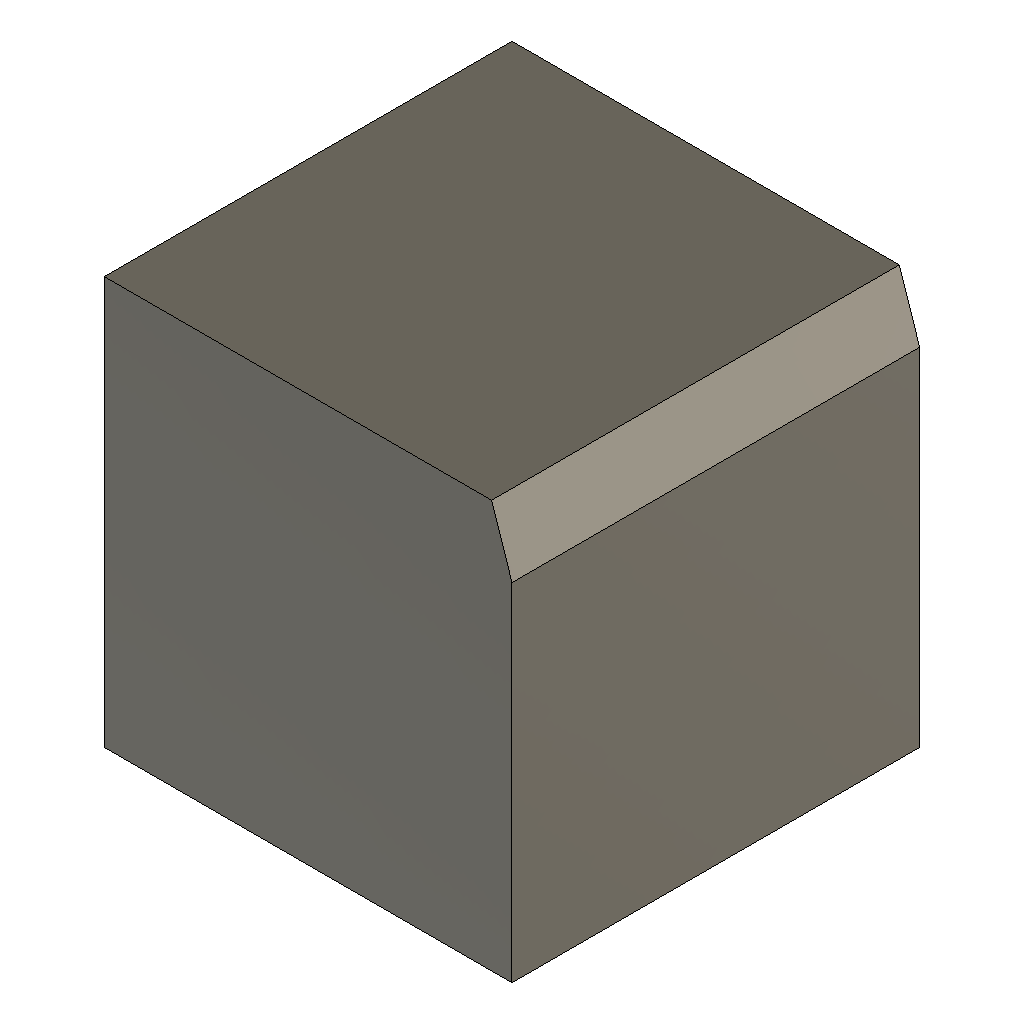
dr341-chamfer-box (Autodesk Fusion 360 design; units mm, degrees)
part number: 2026-11-15-17-11-38-125
Autodesk Fusion 360 part; units mm, degrees
box "BoxPrimitive1" add length 20 width 20 height 20 placed x (0, 1, 0) y (-1, 0, 0) z (0, 0, 1) at (20, 0, 0)
chamfer "Chamfer1" distance 1 distance2 3 1 edges at (20, 10, 20) measured on face at (6.6667, 6.6667, 20) tangent chain off
